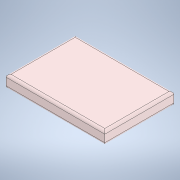
# Autodesk Inventor part: saltea
Saved by Autodesk Inventor 2022.6 (Build 266554000, 554)
## iProperties
Created: 2026-11-02
Part Number: saltea
Material: Generic
Document SubType Name: Modeling
Designer: Dragos Macovei
Density: 1 g/cm^3
Appearance: Default
Author: Dragos Macovei
Autodesk Inventor part; units mm, degrees
ref_plane "YZ Plane" through (0, 0, 0) normal (1, 0, 0) x (0, 1, 0)
ref_plane "XZ Plane" through (0, 0, 0) normal (0, 1, 0) x (-1, 0, 0)
ref_plane "XY Plane" through (0, 0, 0) normal (0, 0, 1) x (1, 0, 0)
sketch "Sketch1" plane through (0, 0, 0) normal (0, 1, 0) x (-1, 0, 0)
  line L0 (0, 0) -> (2000, 0)
  line L1 (2000, 0) -> (2000, 1400)
  line L2 (2000, 1400) -> (0, 1400)
  line L3 (0, 1400) -> (0, 0)
  dimension "d0" = 2000
  dimension "d1" = 1400
  constraints: 8 end point, 2 parallel, 1 horizontal, 1 perpendicular
  measures "d0" distance of L2.end L1.end
  measures "d1" distance of L1.end L0.end
extrude "Extrusion1" add sketch "Sketch1" along normal blind 250
fillet "Fillet1" radius 50 8 edges at (-1000, 250, 1400) (0, 250, 700) (-1000, 250, 0) (-2000, 250, 700) (-1000, 0, 1400) (0, 0, 700) (-2000, 0, 700) (-1000, 0, 0)
body "Solid1"
